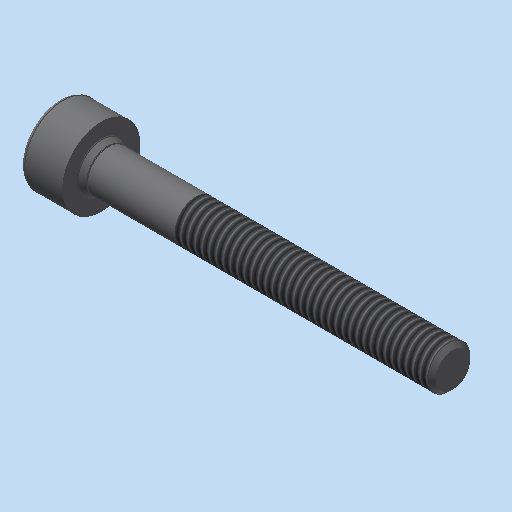
# Autodesk Inventor part: Zylinderschraube_ISO_4762___M3x25
Saved by Autodesk Inventor 2023.3 (Build 273359000, 359)
## iProperties
Shininess: 64.0
Length Units: 11269
Angle Units: 11279
Time Units: 11290
Mass Units: 11283
Length Display Precision: 3
Angle Display Precision: 2
Compacted: True
Part Number: Zylinderschraube_ISO_4762___M3x25
Document SubType Name: Modeling
Created: 2004-04-03
Material: xStahl_AnP_Dummymaterial
Description: =<RBPARTNOTITLE2>
Vendor: NORM8
Designer: S.Riedelsheimer
Manufacturer: Standard
Standards Organization: Custom
Density: 7.85 g/cm^3
Mass: 1.85701 g
Surface Area: 3.45438 cm^2
Volume: 0.236561 cm^3
Appearance: Stahl - normal AnP
DOC_ID: 5 F45 Zylinderschraube_ISO_4762___M3x25
GAIN_REFID: 20__Zylinderschraube_ISO_4762___M3x25:81C07
Control State: 0
Master: False
Checked Out: False
CNS_NB: Zylinderschraube ISO 4762 - M3x25
CNS_NN: ISO 4762
CNS_NT: Zylinderschrauben mit Innensechskant
CNS_NBSYN: Zylinderschraube ISO 4762 - $NENN.
CNS_LINA: Zylinderschraube ISO 4762 - M3x25
CNS_D: 3.000
CNS_D3: 2.387
CNS_P: 0.500
CNS_L: 25.000
CNS_S: 2.500
CNS_HM: 18.000
CNS_DK: 5.500
CNS_DA: 3.600
CNS_DS: 3.000
CNS_E: 2.870
CNS_K: 3.000
CNS_R: 0.100
CNS_T: 1.300
CNS_V: 0.300
CNS_DW: 5.070
CNS_W: 1.150
CNS_LF: 0.510
CNS_LG: 7.000
CNS_FORM: 0.000
CNS_NENN: M3x25
CNS_KT: DUMMY
PSOL_IDENT_0: {C:\partsolutions8\data\23d-libs\bosch_bamberg\schrauben\zylinderschrauben\din_en_iso_4762.prj},170
PSOL_IDENT_1: {M=Nenngewinde},{VTYP=3D},{NB=Zylinderschraube ISO 4762 - M3x25},{NN=ISO 4762},{DATE=26.11.2003},{GE
PSOL_IDENT_2: OMDATE=26.11.2003},{VERSION=v2},{LINEID=350},{LINESUBID=-1},{WBVAR=}  {NB=Zylinderschraube ISO 4762
PSOL_IDENT_3: - M3x25},{LINA=Zylinderschraube ISO 4762 - M3x25},{KT=DUMMY},{IDNR=},{D=3.000},{D3=2.387},{P=0.500},
PSOL_IDENT_4: {L=25.000},{S=2.500},{HM=18.000},{DK=5.500},{DA=3.600},{DS=3.000},{E=2.870},{K=3.000},{R=0.100},{T=1
PSOL_IDENT_5: .300},{V=0.300},{DW=5.070},{W=1.150},{LF=0.510},{LG=7.000},{FORM=0.000},{NENN=M3x25}
DEF_STKID: T21100
Bezeichnung1: Zylinderschraube ISO 4762 - M3x25
Bezeichnung2: Zylinderschrauben mit Innensechskant
RBPARTNOTITLE2: Zylinderschrauben mit Innensechskant
RBPARTNOTITLE1: Hexagon socket head cap screws
AnP_Kategorie: 4
RBDRAWINGMISSINGSPEC: --
RBPARTMADEOF: ISO 4762 - M3x25 - 8.8 verzinkt
Density: 0.0
Volumn: 0.0
Area: 0.0
PropertySet Name: Model Information
Title: Zylinderschraube ISO 4762 - M3x25
Author: S.Riedelsheimer
Keywords: =<RBPARTMADEOF>
Comments: =<RBSURFACE2>
Revision Number: 01
Autodesk Inventor part; units mm, degrees
sketch "Sketch_1" plane through (0, 0, 0) normal (0, 1, 0) x (-1, 0, 0)
  line L0 (-28, 0) -> (6, 0)
  line L1 (0.4283, 0) -> (1.15, -1.25)
  line L2 (1.15, -1.25) -> (2.815, -1.25)
  line L3 (2.815, -1.25) -> (3, -1.435)
  line L4 (3, -1.435) -> (3, -2.45)
  arc A0 (2.7, -2.75) -> (3, -2.45) centre (2.7, -2.45) ccw
  line L5 (2.7, -2.75) -> (0, -2.75)
  line L6 (0, -2.75) -> (0, -1.8)
  arc A1 (0, -1.8) -> (-0.0562, -1.7101) centre (-0.1, -1.8) ccw
  line L7 (-0.0562, -1.7101) -> (-0.4662, -1.5101)
  arc A2 (-0.4662, -1.5101) -> (-0.51, -1.5) centre (-0.51, -1.6) ccw
  line L8 (-0.51, -1.5) -> (-24.6935, -1.5)
  line L9 (-24.6935, -1.5) -> (-25, -1.1935)
  line L10 (-25, -1.1935) -> (-25, 0)
  line L11 (-25, 0) -> (0.4283, 0)
  constraints: 24 end point, 6 point on circle, 3 centre point
revolve "Drehung1" add sketch "Sketch_1" angle 360 about axis through (28, 0, 0) along (1, 0, 0)
thread "Gewinde1" size "M3x0.5" class "6g" standard "ANSI Metric M Profile" length 18
sketch "Skizze_1" plane through (-1.15, 0, 0) normal (1, 0, 0) x (0, 0, -1)
  line L0 (-1.25, 0.7217) -> (-1.25, -0.7217)
  line L1 (-1.25, -0.7217) -> (0, -1.4434)
  line L2 (0, -1.4434) -> (1.25, -0.7217)
  line L3 (1.25, -0.7217) -> (1.25, 0.7217)
  line L4 (1.25, 0.7217) -> (0, 1.4434)
  line L5 (0, 1.4434) -> (-1.25, 0.7217)
  constraints: 12 end point
extrude "Extrusion1" cut sketch "Skizze_1" against normal blind 2.6
ref_plane "IP1_XY" through (0, 0, 0) normal (1, 0, 0) x (0, 0, -1)
ref_plane "IP1_YZ" through (0, 0, 0) normal (0, 0, -1) x (0, 1, 0)
ref_plane "IP3_XY" through (25, 0, 0) normal (1, 0, 0) x (0, 0, -1)
ref_plane "IP3_YZ" through (25, 0, 0) normal (0, 0, -1) x (0, 1, 0)
ref_plane "IP2_XY" through (-3, 0, 0) normal (1, 0, 0) x (0, 0, -1)
ref_plane "IP2_YZ" through (-3, 0, 0) normal (0, 0, -1) x (0, 1, 0)
